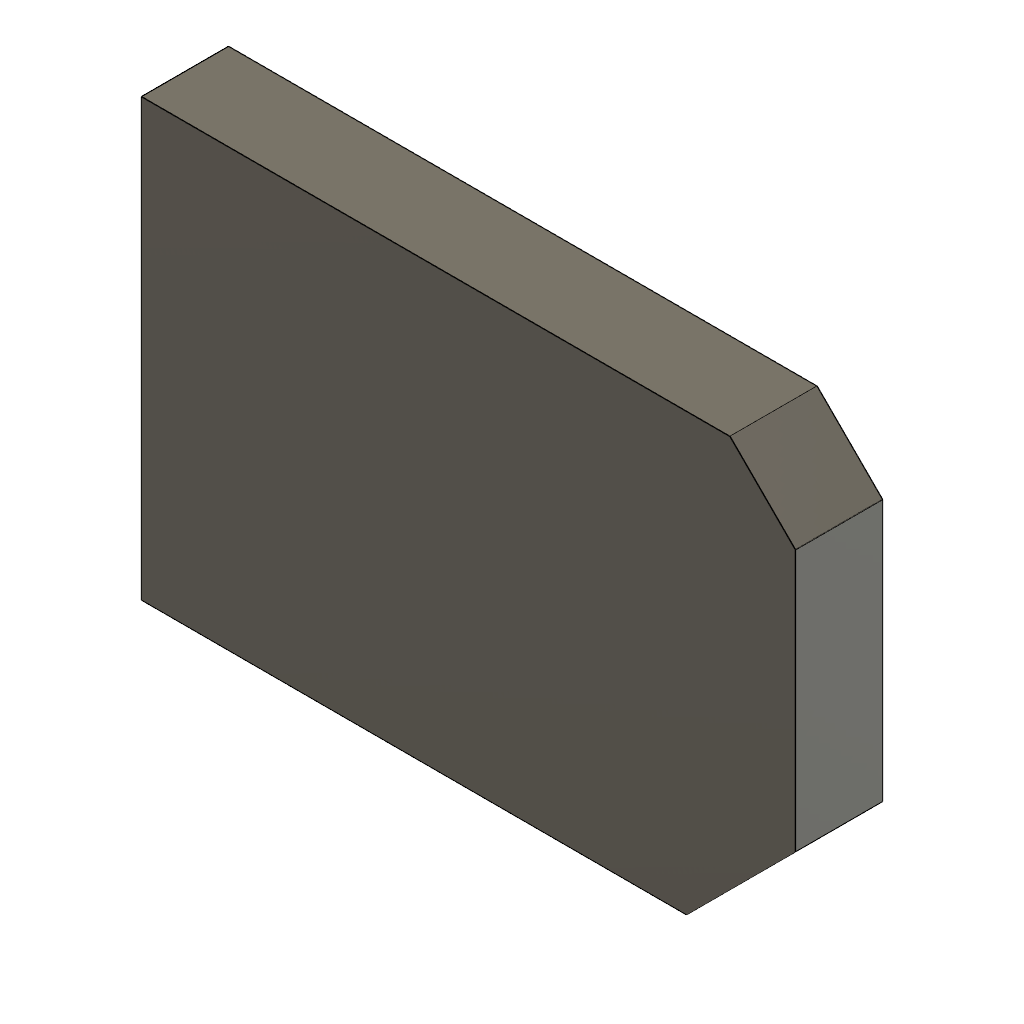
sk_chamfer_corners (Autodesk Fusion 360 design; units mm, degrees)
part number: 2026-11-13-14-36-13-420
Autodesk Fusion 360 part; units mm, degrees
sketch "Sketch1" plane through (0, 0, 0) normal (0, 0, 1) x (1, 0, 0)
  line L0 (0, 0) -> (25, 0)
  line L1 (30, 5) -> (30, 17)
  line L2 (27, 20) -> (0, 20)
  line L3 (0, 20) -> (0, 0)
  line L4 (25, 0) -> (30, 5)
  line L5 (30, 17) -> (27, 20)
  point P0 (30, 0)
  point P1 (30, 20)
  dimension "d1" = 5
  dimension "d2" = 5
  dimension "d3" = 3
  dimension "d4" = 3
  constraint coincident P0 L0
  constraint coincident P0 L1
  constraint coincident P1 L1
  constraint coincident P1 L2
  measures "d1" distance of P0 L0.end
  measures "d2" distance of P0 L1.start
  measures "d3" distance of P1 L1.end
  measures "d4" distance of P1 L2.start
extrude "Extrude1" add sketch "Sketch1" along normal blind 4
